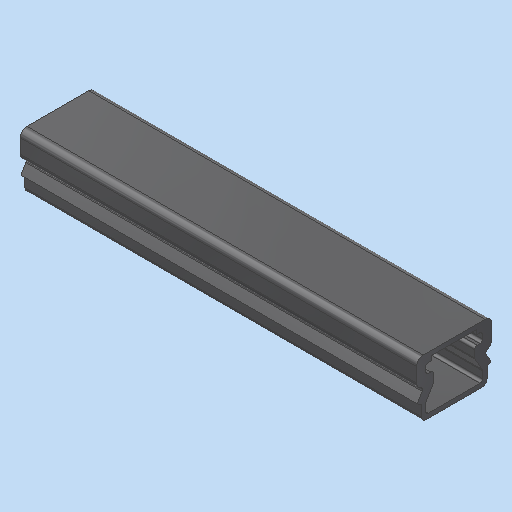
# Autodesk Inventor part: MM0937AN001_G30_702_Kanal-B20025
Saved by Autodesk Inventor 2023.3 (Build 273359000, 359)
## iProperties
Created: 2016-02-09
Part Number: MM0937AN001_G30_702_Kanal-B20025
Material: NORM8
Document SubType Name: Modeling
Designer: fzg9bw
Density: 1.2 g/cm^3
Appearance: Plastik (schwarz)
Description: =<RBPARTNOTITLE2>
Vendor: Hager
Mass: 40.9074 g
Surface Area: 276.707 cm^2
Volume: 34.0895 cm^3
RBMATERIAL: =<Material>
RBMATNO: =<Part Number>
RBPARTMADEOF: Hager B20025-094/10/44723
RBPARTNOTITLE1: wiring canal 25x20
RBPARTNOTITLE2: Kabelkanal 25x20
AnP_Kommentar: Nacharbeit
MaxAbmaße: 0 x 0 x 0 (FM)
AnP_Material_aktuell: =<Material>
AnP_Kommentar_aktuell: =<Comments>
Saegelaenge: 150 mm
AnP_Kategorie: 3
AnP_Material: =<Material>
RBDRAWINGMISSINGSPEC: --
RBSURFACE2: Nacharbeit
Author: fzg9bw
Keywords: =<RBPARTMADEOF>
Comments: =<RBSURFACE2>
Revision Number: 01
Autodesk Inventor part; units mm, degrees
ref_plane "YZ Plane" through (0, 0, 0) normal (1, 0, 0) x (0, 1, 0)
ref_plane "XZ Plane" through (0, 0, 0) normal (0, 1, 0) x (-1, 0, 0)
ref_plane "XY Plane" through (0, 0, 0) normal (0, 0, 1) x (1, 0, 0)
sketch "Skizze1" plane through (0, 0, 0) normal (0, 0, 1) x (1, 0, 0)
  line L0 (-12.5, 0) -> (12.5, 0)
  line L1 (12.5, 0) -> (12.5, 6)
  line L2 (12.5, 6) -> (9.5, 11.1962)
  line L3 (9.5, 11.1962) -> (9.5, 13)
  line L4 (9.5, 13) -> (12.5, 13)
  line L5 (12.5, 13) -> (12.5, 20)
  line L6 (12.5, 20) -> (8.5, 20)
  line L7 (0, 0) -> (0, 10)
  line L8 (0, 0) -> (10, 0) construction
  line L9 (-12.5, 0) -> (-12.5, 6)
  line L10 (-12.5, 6) -> (-9.5, 11.1962)
  line L11 (-9.5, 11.1962) -> (-9.5, 13)
  line L12 (-9.5, 13) -> (-12.5, 13)
  line L13 (-12.5, 13) -> (-12.5, 20)
  line L14 (-12.5, 20) -> (-8.5, 20)
  line L15 (8.5, 18.3) -> (10.8, 18.3)
  line L16 (10.8, 18.3) -> (10.8, 14.7)
  line L17 (10.8, 14.7) -> (7.8, 14.7)
  line L18 (7.8, 14.7) -> (7.8, 10.7406)
  line L19 (7.8, 10.7406) -> (10.8, 5.5445)
  line L20 (10.8, 5.5445) -> (10.8, 1.7)
  line L21 (10.8, 1.7) -> (-10.8, 1.7)
  line L22 (-10.8, 1.7) -> (-10.8, 5.5445)
  line L23 (-10.8, 5.5445) -> (-7.8, 10.7406)
  line L24 (-7.8, 10.7406) -> (-7.8, 14.7)
  line L25 (-7.8, 14.7) -> (-10.8, 14.7)
  line L26 (-10.8, 14.7) -> (-10.8, 18.3)
  line L27 (-10.8, 18.3) -> (-8.5, 18.3)
  line L28 (8.5, 20) -> (8.5, 18.3)
  line L29 (-8.5, 20) -> (-8.5, 18.3)
  point P0 (0, 0)
  point P1 (0, 0)
  dimension "d4" = 7
  dimension "d5" = 7
  dimension "d6" = 30
  dimension "d7" = 4
  dimension "d8" = 90
  dimension "d9" = 1.7
  dimension "d10" = 20
  dimension "d11" = 1.7
  dimension "d13" = 1.7
  dimension "d14" = 25
  dimension "d17" = 3
  dimension "d29" = 10
  constraints: 60 end point, 6 symmetric about line, 4 vertical, 2 coincident, 2 equal length, 2 horizontal, 1 collinear, 1 midpoint, 1 perpendicular, 1 point on line, 10 other
  measures "d4" distance between parallel lines of L6 L4
  measures "d5" distance from line of L4 L1.end
  measures "d6" angle of L2 L1
  measures "d7" distance of L6.end L5.end
  measures "d8" angle of L8 L7
  measures "d9" distance between parallel lines of L15 L6
  measures "d10" distance between parallel lines of L6 L0
  measures "d11" distance between parallel lines of L5 L16
  measures "d13" distance between parallel lines of L14 L27
  measures "d14" distance between parallel lines of L1 L9
  measures "d17" distance between parallel lines of L3 L5
  measures "d29" distance of L7.start L7.end
extrude "Laenge   HIER EINGEBEN" add sketch "Skizze1" along normal blind 150
sketch "Skizze2" plane through (0, 0, 0) normal (0, 0, 1) x (1, 0, 0)
  line L0 (12.5, 0) -> (12.5, 6) projected
  line L1 (12.5, 6) -> (9.5, 11.1962) projected
  line L2 (9.5, 11.1962) -> (9.5, 13) projected
  line L3 (9.5, 13) -> (12.5, 13) projected
  line L4 (12.5, 13) -> (12.5, 20) projected
  line L5 (12.5, 20) -> (8.5, 20) projected
  line L6 (8.5, 20) -> (8.5, 18.3) projected
  line L7 (8.5, 18.3) -> (10.8, 18.3) projected
  line L8 (10.8, 18.3) -> (10.8, 14.7) projected
  line L9 (10.8, 14.7) -> (7.8, 14.7) projected
  line L10 (7.8, 14.7) -> (7.8, 10.7406) projected
  line L11 (7.8, 10.7406) -> (10.8, 5.5445) projected
  line L12 (10.8, 5.5445) -> (10.8, 1.7) projected
  line L13 (10.8, 1.7) -> (-10.8, 1.7) projected
  line L14 (-10.8, 1.7) -> (-10.8, 5.5445) projected
  line L15 (-10.8, 5.5445) -> (-7.8, 10.7406) projected
  line L16 (-7.8, 10.7406) -> (-7.8, 14.7) projected
  line L17 (-7.8, 14.7) -> (-10.8, 14.7) projected
  line L18 (-10.8, 14.7) -> (-10.8, 18.3) projected
  line L19 (-10.8, 18.3) -> (-8.5, 18.3) projected
  line L20 (-8.5, 18.3) -> (-8.5, 20) projected
  line L21 (-8.5, 20) -> (-12.5, 20) projected
  line L22 (-12.5, 20) -> (-12.5, 13) projected
  line L23 (-12.5, 13) -> (-9.5, 13) projected
  line L24 (-9.5, 13) -> (-9.5, 11.1962) projected
  line L25 (-9.5, 11.1962) -> (-12.5, 6) projected
  line L26 (-12.5, 6) -> (-12.5, 0) projected
  line L27 (-12.5, 0) -> (12.5, 0) projected
  line L28 (-14.2, 21.7) -> (3.2, 21.7)
  line L29 (-14.2, 21.7) -> (14.2, 21.7)
  line L30 (14.2, 21.7) -> (14.2, 11.3)
  line L31 (14.2, 11.3) -> (11.403, 11.3)
  line L32 (11.403, 11.3) -> (13.9722, 6.85)
  line L33 (-13.9722, 6.85) -> (-11.403, 11.3)
  line L34 (-11.403, 11.3) -> (-14.2, 11.3)
  line L35 (-14.2, 11.3) -> (-14.2, 21.7)
  line L36 (-12.5, 20) -> (12.5, 20)
  line L37 (12.5, 20) -> (12.5, 13)
  line L38 (12.5, 13) -> (9.5, 13)
  line L39 (9.5, 13) -> (9.5, 11.1962)
  line L40 (9.5, 11.1962) -> (12.5, 6)
  line L41 (12.5, 6) -> (13.9722, 6.85)
  line L42 (-12.5, 20) -> (-12.5, 13)
  line L43 (-12.5, 13) -> (-9.5, 13)
  line L44 (-9.5, 13) -> (-9.5, 11.1962)
  line L45 (-9.5, 11.1962) -> (-12.5, 6)
  line L46 (-12.5, 6) -> (-13.9722, 6.85)
  point P0 (0, 0)
  dimension "d21" = 1.7
  dimension "d22" = 28.4
  dimension "d30" = 1.7
  constraints: 38 end point, 2 point on line, 2 other
  measures "d21" distance between parallel lines of L28 L21
  measures "d22" distance between parallel lines of L30 L35
  measures "d30" distance between parallel lines of L32 L1
extrude "Deckel  KANN UNTERDRÜCKT WERDEN" add sketch "Skizze2" along normal blind 150 contours L1 L2 L3 L4 L5 L36 L21 L22 L23 L24 L25 L46 L33 L34 L35 L28 L29 L30 L31 L32 L41
fillet "Rundung1" radius 2 2 edges at (12.5, 0, 75) (-12.5, 0, 75)
fillet "Rundung2" radius 1 12 edges at (-10.8, 1.7, 75) (10.8, 1.7, 75) (7.8, 14.7, 75) (-7.8, 14.7, 75) (-7.8, 10.7406, 75) (-10.8, 5.5445, 75) (-10.8, 18.3, 75) (10.8, 18.3, 75) (7.8, 10.7406, 75) (10.8, 5.5445, 75) (-10.8, 14.7, 75) (10.8, 14.7, 75)
fillet "Rundung3" radius 2.5 4 edges at (-14.2, 21.7, 75) (-14.2, 11.3, 75) (14.2, 21.7, 75) (14.2, 11.3, 75)
fillet "Rundung4" radius 1 2 edges at (-11.403, 11.3, 75) (11.403, 11.3, 75)
equation "\"d23\" = Saegelaenge"
equation "\"Saegelaenge\" = 150"
